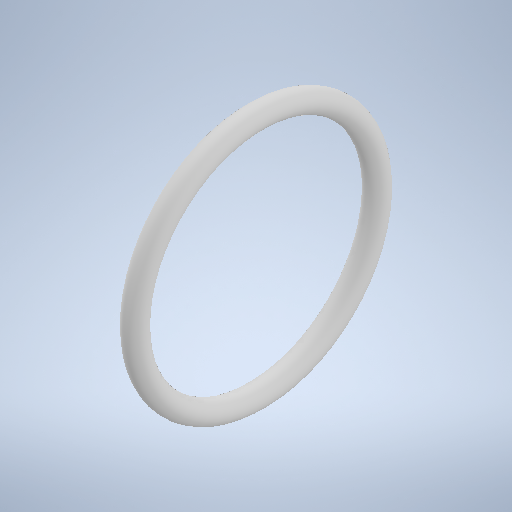
# Autodesk Inventor part: InputSeal
Saved by Autodesk Inventor 2025 (Build 290162000, 162)
## iProperties
Created: 2024-05-30
Part Number: InputSeal
Material: Generic
Document SubType Name: Modeling
Designer: BenFr
Density: 1 g/cm^3
Appearance: Default
Author: BenFr
Autodesk Inventor part; units mm, degrees
ref_plane "YZ Plane" through (0, 0, 0) normal (1, 0, 0) x (0, 1, 0)
ref_plane "XZ Plane" through (0, 0, 0) normal (0, 1, 0) x (-1, 0, 0)
ref_plane "XY Plane" through (0, 0, 0) normal (0, 0, 1) x (1, 0, 0)
sketch "Sketch1" plane through (0, 0, 0) normal (0, 1, 0) x (-1, 0, 0)
  circle A0 centre (0, 22.5) radius 2
  line L0 (2.8, 0) -> (-2.8, 0) projected
  point P0 (0, 0)
  dimension "d0" = 4
  dimension "d2" = 22.5
  constraints: 1 centre point
  measures "d0" diameter of A0
  measures "d2" distance of point (0, 0) A0.centre
revolve "Revolution1" add sketch "Sketch1" angle 360 about axis through (-10, 0, 0) along (1, 0, 0)
body "Solid1"
